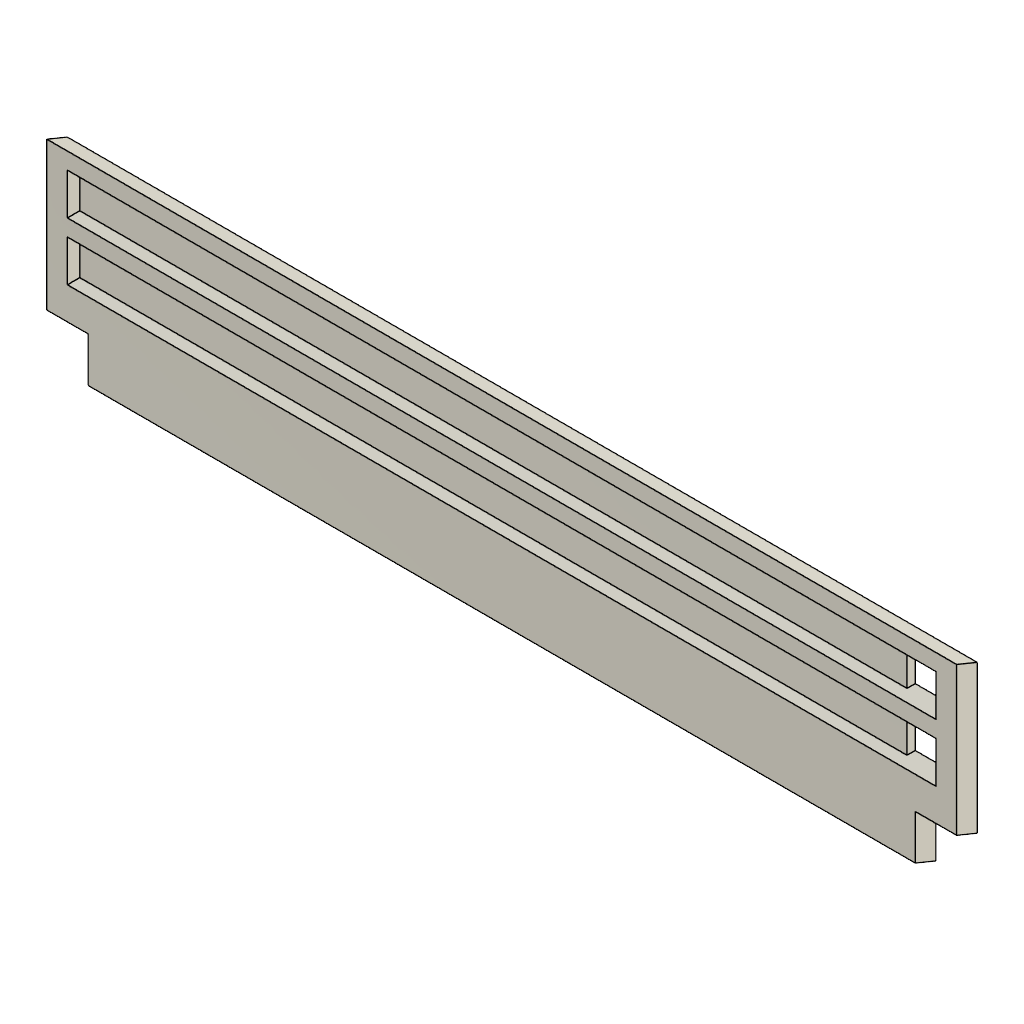
name_sign_LED_holder_top_front (Autodesk Fusion 360 design; units mm, degrees)
part number: 2026-10-25-15-26-22-685
Autodesk Fusion 360 part; units mm, degrees
sketch "Name sign LED holder top front" plane through (0, 0, 0) normal (1, 0, 0) x (0, 1, 0)
  line L0 (5, 46.5964) -> (5, 0.0004)
  line L1 (5, 0.0004) -> (0, 2.051)
  line L2 (0, 2.051) -> (0, 48.647)
  line L3 (0, 48.647) -> (5, 46.5964)
  dimension "d2" = 46.596
  dimension "d3" = 112.3
  dimension "d26" = 112.3
  dimension "d27" = 5
  constraint parallel L0 L2
  measures "d2" distance of L2.end L1.end
  measures "d3" angle of L1 L2
  measures "d26" angle of L2 L3
  measures "d27" distance of L0 L2
extrude "Extrude1" add sketch "Name sign LED holder top front" along normal blind 220
sketch "LED grooves" plane through (0, 0, 0) normal (0, -1, 0) x (1, 0, 0)
  line L0 (0, 48.647) -> (0, 2.051)
  line L1 (0, 2.051) -> (220, 2.051)
  line L2 (220, 2.051) -> (220, 48.647)
  line L3 (5, 44.647) -> (215, 44.647)
  line L4 (215, 44.647) -> (215, 34.647)
  line L5 (215, 34.647) -> (5, 34.647)
  line L6 (5, 34.647) -> (5, 44.647)
  line L7 (5, 30.647) -> (215, 30.647)
  line L8 (215, 30.647) -> (215, 20.647)
  line L9 (215, 20.647) -> (5, 20.647)
  line L10 (5, 20.647) -> (5, 30.647)
  line L11 (215, 44.647) -> (205, 44.647)
  line L12 (205, 44.647) -> (205, 34.647)
  line L13 (205, 34.647) -> (215, 34.647)
  line L14 (215, 34.647) -> (215, 44.647)
  line L15 (215, 30.647) -> (205, 30.647)
  line L16 (205, 30.647) -> (205, 20.647)
  line L17 (205, 20.647) -> (215, 20.647)
  line L18 (215, 20.647) -> (215, 30.647)
  line L19 (220, 48.647) -> (0, 48.647)
  dimension "d8" = 5
  dimension "d9" = 210
  dimension "d10" = 5
  dimension "d11" = 10
  dimension "d12" = 10
  dimension "d14" = 4
  dimension "d15" = 10
  dimension "d28" = 4
  constraint horizontal L3
  constraint vertical L4
  constraint horizontal L5
  constraint vertical L6
  constraint horizontal L7
  constraint vertical L8
  constraint horizontal L9
  constraint vertical L10
  constraint collinear L6 L10
  constraint collinear L4 L8
  constraint horizontal L11
  constraint vertical L12
  constraint horizontal L13
  constraint vertical L14
  constraint coincident L5 L12.end
  constraint horizontal L15
  constraint vertical L16
  constraint horizontal L17
  constraint vertical L18
  constraint coincident L9 L16.end
  constraint collinear L12 L16
  measures "d8" distance of L0 L6
  measures "d9" distance of L3.start L3.end
  measures "d10" distance of L2 L4
  measures "d11" distance of L3.start L5.end
  measures "d12" distance of L7.start L9.end
  measures "d14" distance of L5 L7
  measures "d15" distance of L12 L14
  measures "d28" distance of L3 L19
extrude "Extrude2" cut sketch "LED grooves" against normal blind 3 contours L3 L5 L6 L12 | L7 L9 L10 L16
extrude "Extrude3" cut sketch "LED grooves" against normal blind 5 contours L3 L4 L5 L11 L12 L13 L14 | L7 L8 L9 L15 L16 L17 L18
sketch "Support" plane through (220, 0, 0) normal (1, 0, 0) x (0, 1, 0)
  line L0 (0, 2.051) -> (5, 0.0004)
  line L1 (5, 0.0004) -> (5, 46.5964)
  line L2 (0, 48.647) -> (0, 2.051)
  line L3 (0, 12.859) -> (5, 10.8084)
  line L4 (0, 12.859) -> (0, 2.051)
  line L5 (0, 2.051) -> (5, 0.0004)
  line L6 (5, 0.0004) -> (5, 10.8084)
  line L7 (5, 46.5964) -> (0, 48.647)
  dimension "d20" = 10.808
  constraint coincident L2 L3.start
  constraint coincident L1 L3.end
  constraint parallel L0 L3
  constraint coincident L0.start L2.end
  constraint coincident L0.end L1.start
  measures "d20" distance of L0.start L3.start
extrude "Extrude4" cut sketch "Support" against normal blind 10 contours L0 L1 L2 L3 L4 L5 L6
extrude "Extrude5" cut sketch "Support" against normal blind 10 from surface at -210 contours L0 L1 L2 L3 L4 L5 L6
named bodies: "Name sign LED holder top front"
